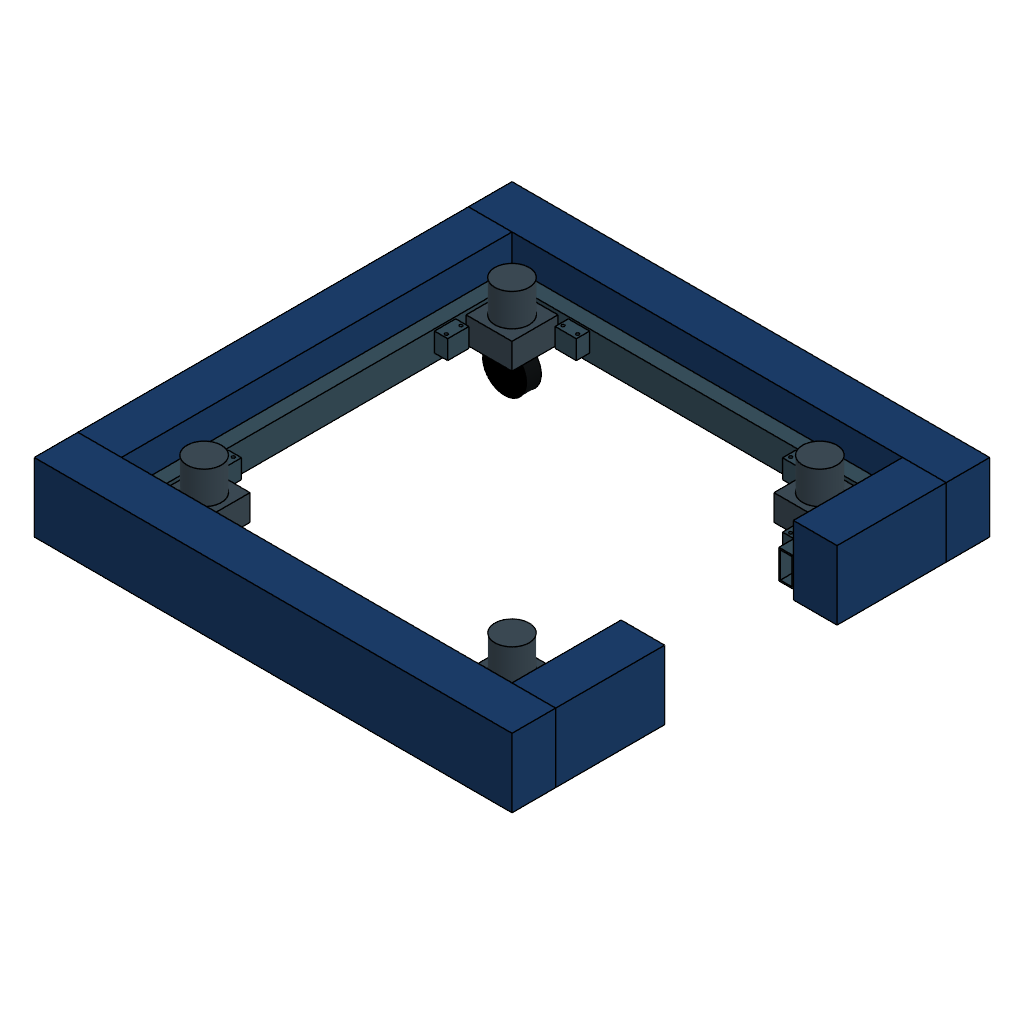
own-zone-public (Autodesk Fusion 360 design; units mm, degrees)
part number: 2026-11-19-16-10-08-669
part number: 2026-11-19-16-10-12-330
part number: 2026-11-19-16-10-12-467
part number: 2026-11-19-16-10-12-522
part number: 2026-11-19-16-10-12-574
part number: 2026-11-19-16-10-12-622
part number: 2026-11-19-16-10-12-689
part number: 2026-11-19-16-10-12-752
part number: 2026-11-19-16-10-12-805
part number: 2026-11-19-16-10-12-862
part number: 2026-11-19-16-10-12-931
part number: 2026-11-19-16-10-13-004
part number: 2026-11-19-16-10-13-091
part number: 2026-11-19-16-10-13-172
part number: 2026-11-19-16-10-13-257
part number: 2026-11-19-16-10-13-348
part number: 2026-11-19-16-10-13-447
part number: 2026-11-19-16-10-13-556
part number: 2026-11-19-16-10-13-649
part number: 2026-11-19-16-10-13-740
part number: 2026-11-19-16-10-13-823
part number: 2026-11-19-16-10-13-917
part number: 2026-11-19-16-10-14-002
part number: 2026-11-19-16-10-14-092
part number: 2026-11-19-16-10-14-189
part number: 2026-11-19-16-10-14-316
part number: 2026-11-19-16-10-14-442
part number: 2026-11-19-16-10-14-569
part number: 2026-11-19-16-10-14-696
part number: 2026-11-19-16-10-14-815
part number: 2026-11-19-16-10-14-952
Autodesk Fusion 360 part; units mm, degrees
sketch "Editable cross section" plane through (0, 0, 0) normal (0, 0, 1) x (1, 0, 0) in component "left perimeter tube"
  line L0 (-12.7, -25.4) -> (12.7, -25.4)
  line L1 (12.7, -25.4) -> (12.7, 25.4)
  line L2 (12.7, 25.4) -> (-12.7, 25.4)
  line L3 (-12.7, 25.4) -> (-12.7, -25.4)
  line L4 (-10.16, -22.86) -> (10.16, -22.86)
  line L5 (10.16, -22.86) -> (10.16, 22.86)
  line L6 (10.16, 22.86) -> (-10.16, 22.86)
  line L7 (-10.16, 22.86) -> (-10.16, -22.86)
extrude "Stock length" add sketch "Editable cross section" along normal blind 680 makes body 1 in component "left perimeter tube"
sketch "Editable cross section (2)" plane through (0, 0, 0) normal (0, 0, 1) x (1, 0, 0) in component "left front return"
  line L0 (-12.7, -25.4) -> (12.7, -25.4)
  line L1 (12.7, -25.4) -> (12.7, 25.4)
  line L2 (12.7, 25.4) -> (-12.7, 25.4)
  line L3 (-12.7, 25.4) -> (-12.7, -25.4)
  line L4 (-10.16, -22.86) -> (10.16, -22.86)
  line L5 (10.16, -22.86) -> (10.16, 22.86)
  line L6 (10.16, 22.86) -> (-10.16, 22.86)
  line L7 (-10.16, 22.86) -> (-10.16, -22.86)
extrude "Stock length'" add sketch "Editable cross section (2)" along normal blind 164.6 separate body makes body 2 in component "left front return"
sketch "Editable cross section (3)" plane through (0, 0, 0) normal (0, 0, 1) x (1, 0, 0) in component "left blue side bumper"
  line L0 (-416, -38) -> (416, -38)
  line L1 (416, -38) -> (416, 38)
  line L2 (416, 38) -> (-416, 38)
  line L3 (-416, 38) -> (-416, -38)
extrude "Stock length''" add sketch "Editable cross section (3)" along normal blind 120 separate body makes body 3 in component "left blue side bumper"
sketch "Editable cross section (4)" plane through (0, 0, 0) normal (0, 0, 1) x (1, 0, 0) in component "left blue front bumper"
  line L0 (-38, -95) -> (38, -95)
  line L1 (38, -95) -> (38, 95)
  line L2 (38, 95) -> (-38, 95)
  line L3 (-38, 95) -> (-38, -95)
extrude "Stock length'''" add sketch "Editable cross section (4)" along normal blind 120 separate body makes body 4 in component "left blue front bumper"
sketch "Editable cross section (5)" plane through (0, 0, 0) normal (0, 0, 1) x (1, 0, 0) in component "right perimeter tube"
  line L0 (-12.7, -25.4) -> (12.7, -25.4)
  line L1 (12.7, -25.4) -> (12.7, 25.4)
  line L2 (12.7, 25.4) -> (-12.7, 25.4)
  line L3 (-12.7, 25.4) -> (-12.7, -25.4)
  line L4 (-10.16, -22.86) -> (10.16, -22.86)
  line L5 (10.16, -22.86) -> (10.16, 22.86)
  line L6 (10.16, 22.86) -> (-10.16, 22.86)
  line L7 (-10.16, 22.86) -> (-10.16, -22.86)
extrude "Stock length''''" add sketch "Editable cross section (5)" along normal blind 680 separate body makes body 5 in component "right perimeter tube"
sketch "Editable cross section (6)" plane through (0, 0, 0) normal (0, 0, 1) x (1, 0, 0) in component "right front return"
  line L0 (-12.7, -25.4) -> (12.7, -25.4)
  line L1 (12.7, -25.4) -> (12.7, 25.4)
  line L2 (12.7, 25.4) -> (-12.7, 25.4)
  line L3 (-12.7, 25.4) -> (-12.7, -25.4)
  line L4 (-10.16, -22.86) -> (10.16, -22.86)
  line L5 (10.16, -22.86) -> (10.16, 22.86)
  line L6 (10.16, 22.86) -> (-10.16, 22.86)
  line L7 (-10.16, 22.86) -> (-10.16, -22.86)
extrude "Stock length'''''" add sketch "Editable cross section (6)" along normal blind 164.6 separate body makes body 6 in component "right front return"
sketch "Editable cross section (7)" plane through (0, 0, 0) normal (0, 0, 1) x (1, 0, 0) in component "right blue side bumper"
  line L0 (-416, -38) -> (416, -38)
  line L1 (416, -38) -> (416, 38)
  line L2 (416, 38) -> (-416, 38)
  line L3 (-416, 38) -> (-416, -38)
extrude "Stock length''''''" add sketch "Editable cross section (7)" along normal blind 120 separate body makes body 7 in component "right blue side bumper"
sketch "Editable cross section (8)" plane through (0, 0, 0) normal (0, 0, 1) x (1, 0, 0) in component "right blue front bumper"
  line L0 (-38, -95) -> (38, -95)
  line L1 (38, -95) -> (38, 95)
  line L2 (38, 95) -> (-38, 95)
  line L3 (-38, 95) -> (-38, -95)
extrude "Stock length'''''''" add sketch "Editable cross section (8)" along normal blind 120 separate body makes body 8 in component "right blue front bumper"
sketch "Editable cross section (9)" plane through (0, 0, 0) normal (0, 0, 1) x (1, 0, 0) in component "rear perimeter tube"
  line L0 (-12.7, -25.4) -> (12.7, -25.4)
  line L1 (12.7, -25.4) -> (12.7, 25.4)
  line L2 (12.7, 25.4) -> (-12.7, 25.4)
  line L3 (-12.7, 25.4) -> (-12.7, -25.4)
  line L4 (-10.16, -22.86) -> (10.16, -22.86)
  line L5 (10.16, -22.86) -> (10.16, 22.86)
  line L6 (10.16, 22.86) -> (-10.16, 22.86)
  line L7 (-10.16, 22.86) -> (-10.16, -22.86)
extrude "Stock length''''''''" add sketch "Editable cross section (9)" along normal blind 629.2 separate body makes body 9 in component "rear perimeter tube"
sketch "Editable cross section (10)" plane through (0, 0, 0) normal (0, 0, 1) x (1, 0, 0) in component "rear blue bumper"
  line L0 (-38, -340) -> (38, -340)
  line L1 (38, -340) -> (38, 340)
  line L2 (38, 340) -> (-38, 340)
  line L3 (-38, 340) -> (-38, -340)
extrude "Stock length'''''''''" add sketch "Editable cross section (10)" along normal blind 120 separate body makes body 10 in component "rear blue bumper"
sketch "Editable cross section (11)" plane through (0, 0, 0) normal (0, 0, 1) x (1, 0, 0) in component "front left module tab spacer 1"
  line L0 (-18.5, -11.55) -> (18.5, -11.55)
  line L1 (18.5, -11.55) -> (18.5, 11.55)
  line L2 (18.5, 11.55) -> (-18.5, 11.55)
  line L3 (-18.5, 11.55) -> (-18.5, -11.55)
  circle A0 centre (12.85, -3.3) radius 2.65
  circle A1 centre (-12.55, -3.3) radius 2.65
extrude "Stock length''''''''''" add sketch "Editable cross section (11)" along normal blind 33.18 separate body makes body 11 in component "front left module tab spacer 1"
sketch "Editable cross section (12)" plane through (0, 0, 0) normal (0, 0, 1) x (1, 0, 0) in component "front left module tab spacer 2"
  line L0 (-11.55, -18.5) -> (11.55, -18.5)
  line L1 (11.55, -18.5) -> (11.55, 18.5)
  line L2 (11.55, 18.5) -> (-11.55, 18.5)
  line L3 (-11.55, 18.5) -> (-11.55, -18.5)
  circle A0 centre (-3.3, 12.85) radius 2.65
  circle A1 centre (-3.3, -12.55) radius 2.65
extrude "Stock length'''''''''''" add sketch "Editable cross section (12)" along normal blind 33.18 separate body makes body 12 in component "front left module tab spacer 2"
sketch "Editable cross section (13)" plane through (0, 0, 0) normal (0, 0, 1) x (1, 0, 0) in component "front right module tab spacer 1"
  line L0 (-11.55, -18.5) -> (11.55, -18.5)
  line L1 (11.55, -18.5) -> (11.55, 18.5)
  line L2 (11.55, 18.5) -> (-11.55, 18.5)
  line L3 (-11.55, 18.5) -> (-11.55, -18.5)
  circle A0 centre (-3.3, -12.85) radius 2.65
  circle A1 centre (-3.3, 12.55) radius 2.65
extrude "Stock length''''''''''''" add sketch "Editable cross section (13)" along normal blind 33.18 separate body makes body 13 in component "front right module tab spacer 1"
sketch "Editable cross section (14)" plane through (0, 0, 0) normal (0, 0, 1) x (1, 0, 0) in component "front right module tab spacer 2"
  line L0 (-18.5, -11.55) -> (18.5, -11.55)
  line L1 (18.5, -11.55) -> (18.5, 11.55)
  line L2 (18.5, 11.55) -> (-18.5, 11.55)
  line L3 (-18.5, 11.55) -> (-18.5, -11.55)
  circle A0 centre (12.85, 3.3) radius 2.65
  circle A1 centre (-12.55, 3.3) radius 2.65
extrude "Stock length'''''''''''''" add sketch "Editable cross section (14)" along normal blind 33.18 separate body makes body 14 in component "front right module tab spacer 2"
sketch "Editable cross section (15)" plane through (0, 0, 0) normal (0, 0, 1) x (1, 0, 0) in component "rear left module tab spacer 1"
  line L0 (-11.55, -18.5) -> (11.55, -18.5)
  line L1 (11.55, -18.5) -> (11.55, 18.5)
  line L2 (11.55, 18.5) -> (-11.55, 18.5)
  line L3 (-11.55, 18.5) -> (-11.55, -18.5)
  circle A0 centre (3.3, 12.85) radius 2.65
  circle A1 centre (3.3, -12.55) radius 2.65
extrude "Stock length''''''''''''''" add sketch "Editable cross section (15)" along normal blind 33.18 separate body makes body 15 in component "rear left module tab spacer 1"
sketch "Editable cross section (16)" plane through (0, 0, 0) normal (0, 0, 1) x (1, 0, 0) in component "rear left module tab spacer 2"
  line L0 (-18.5, -11.55) -> (18.5, -11.55)
  line L1 (18.5, -11.55) -> (18.5, 11.55)
  line L2 (18.5, 11.55) -> (-18.5, 11.55)
  line L3 (-18.5, 11.55) -> (-18.5, -11.55)
  circle A0 centre (-12.85, -3.3) radius 2.65
  circle A1 centre (12.55, -3.3) radius 2.65
extrude "Stock length'''''''''''''''" add sketch "Editable cross section (16)" along normal blind 33.18 separate body makes body 16 in component "rear left module tab spacer 2"
sketch "Editable cross section (17)" plane through (0, 0, 0) normal (0, 0, 1) x (1, 0, 0) in component "rear right module tab spacer 1"
  line L0 (-18.5, -11.55) -> (18.5, -11.55)
  line L1 (18.5, -11.55) -> (18.5, 11.55)
  line L2 (18.5, 11.55) -> (-18.5, 11.55)
  line L3 (-18.5, 11.55) -> (-18.5, -11.55)
  circle A0 centre (-12.85, 3.3) radius 2.65
  circle A1 centre (12.55, 3.3) radius 2.65
extrude "Stock length''''''''''''''''" add sketch "Editable cross section (17)" along normal blind 33.18 separate body makes body 17 in component "rear right module tab spacer 1"
sketch "Editable cross section (18)" plane through (0, 0, 0) normal (0, 0, 1) x (1, 0, 0) in component "rear right module tab spacer 2"
  line L0 (-11.55, -18.5) -> (11.55, -18.5)
  line L1 (11.55, -18.5) -> (11.55, 18.5)
  line L2 (11.55, 18.5) -> (-11.55, 18.5)
  line L3 (-11.55, 18.5) -> (-11.55, -18.5)
  circle A0 centre (3.3, -12.85) radius 2.65
  circle A1 centre (3.3, 12.55) radius 2.65
extrude "Stock length'''''''''''''''''" add sketch "Editable cross section (18)" along normal blind 33.18 separate body makes body 18 in component "rear right module tab spacer 2"
sketch "Editable cross section (19)" plane through (0, 0, 0) normal (0, 0, 1) x (1, 0, 0) in component "front left public wheel"
  circle A0 centre (0, 0) radius 38.1
extrude "Stock length''''''''''''''''''" add sketch "Editable cross section (19)" along normal blind 26 separate body makes body 19 in component "front left public wheel"
sketch "Editable cross section (20)" plane through (0, 0, 0) normal (0, 0, 1) x (1, 0, 0) in component "front left public drive housing"
  line L0 (-40, -40) -> (40, -40)
  line L1 (40, -40) -> (40, 40)
  line L2 (40, 40) -> (-40, 40)
  line L3 (-40, 40) -> (-40, -40)
extrude "Stock length'''''''''''''''''''" add sketch "Editable cross section (20)" along normal blind 45 separate body makes body 20 in component "front left public drive housing"
sketch "Editable cross section (21)" plane through (0, 0, 0) normal (0, 0, 1) x (1, 0, 0) in component "front left public motor reserve"
  circle A0 centre (0, 0) radius 29.9
extrude "Stock length''''''''''''''''''''" add sketch "Editable cross section (21)" along normal blind 56.46 separate body makes body 21 in component "front left public motor reserve"
sketch "Editable cross section (22)" plane through (0, 0, 0) normal (0, 0, 1) x (1, 0, 0) in component "front right public wheel"
  circle A0 centre (0, 0) radius 38.1
extrude "Stock length'''''''''''''''''''''" add sketch "Editable cross section (22)" along normal blind 26 separate body makes body 22 in component "front right public wheel"
sketch "Editable cross section (23)" plane through (0, 0, 0) normal (0, 0, 1) x (1, 0, 0) in component "front right public drive housing"
  line L0 (-40, -40) -> (40, -40)
  line L1 (40, -40) -> (40, 40)
  line L2 (40, 40) -> (-40, 40)
  line L3 (-40, 40) -> (-40, -40)
extrude "Stock length''''''''''''''''''''''" add sketch "Editable cross section (23)" along normal blind 45 separate body makes body 23 in component "front right public drive housing"
sketch "Editable cross section (24)" plane through (0, 0, 0) normal (0, 0, 1) x (1, 0, 0) in component "front right public motor reserve"
  circle A0 centre (0, 0) radius 29.9
extrude "Stock length'''''''''''''''''''''''" add sketch "Editable cross section (24)" along normal blind 56.46 separate body makes body 24 in component "front right public motor reserve"
sketch "Editable cross section (25)" plane through (0, 0, 0) normal (0, 0, 1) x (1, 0, 0) in component "rear left public wheel"
  circle A0 centre (0, 0) radius 38.1
extrude "Stock length''''''''''''''''''''''''" add sketch "Editable cross section (25)" along normal blind 26 separate body makes body 25 in component "rear left public wheel"
sketch "Editable cross section (26)" plane through (0, 0, 0) normal (0, 0, 1) x (1, 0, 0) in component "rear left public drive housing"
  line L0 (-40, -40) -> (40, -40)
  line L1 (40, -40) -> (40, 40)
  line L2 (40, 40) -> (-40, 40)
  line L3 (-40, 40) -> (-40, -40)
extrude "Stock length'''''''''''''''''''''''''" add sketch "Editable cross section (26)" along normal blind 45 separate body makes body 26 in component "rear left public drive housing"
sketch "Editable cross section (27)" plane through (0, 0, 0) normal (0, 0, 1) x (1, 0, 0) in component "rear left public motor reserve"
  circle A0 centre (0, 0) radius 29.9
extrude "Stock length''''''''''''''''''''''''''" add sketch "Editable cross section (27)" along normal blind 56.46 separate body makes body 27 in component "rear left public motor reserve"
sketch "Editable cross section (28)" plane through (0, 0, 0) normal (0, 0, 1) x (1, 0, 0) in component "rear right public wheel"
  circle A0 centre (0, 0) radius 38.1
extrude "Stock length'''''''''''''''''''''''''''" add sketch "Editable cross section (28)" along normal blind 26 separate body makes body 28 in component "rear right public wheel"
sketch "Editable cross section (29)" plane through (0, 0, 0) normal (0, 0, 1) x (1, 0, 0) in component "rear right public drive housing"
  line L0 (-40, -40) -> (40, -40)
  line L1 (40, -40) -> (40, 40)
  line L2 (40, 40) -> (-40, 40)
  line L3 (-40, 40) -> (-40, -40)
extrude "Stock length''''''''''''''''''''''''''''" add sketch "Editable cross section (29)" along normal blind 45 separate body makes body 29 in component "rear right public drive housing"
sketch "Editable cross section (30)" plane through (0, 0, 0) normal (0, 0, 1) x (1, 0, 0) in component "rear right public motor reserve"
  circle A0 centre (0, 0) radius 29.9
extrude "Stock length'''''''''''''''''''''''''''''" add sketch "Editable cross section (30)" along normal blind 56.46 separate body makes body 30 in component "rear right public motor reserve"
component "left perimeter tube" placed x (0, 1, 0) y (0, 0, 1) z (1, 0, 0) at (-340, 327.3, 89.4)
component "left front return" placed x (-1, 0, 0) y (0, 0, 1) z (0, 1, 0) at (327.3, 150, 89.4)
component "left blue side bumper" placed x (1, 0, 0) y (0, 1, 0) z (0, 0, 1) at (0, 378, 48)
component "left blue front bumper" placed x (1, 0, 0) y (0, 1, 0) z (0, 0, 1) at (378, 245, 48)
component "right perimeter tube" placed x (0, 1, 0) y (0, 0, 1) z (1, 0, 0) at (-340, -327.3, 89.4)
component "right front return" placed x (-1, 0, 0) y (0, 0, 1) z (0, 1, 0) at (327.3, -314.6, 89.4)
component "right blue side bumper" placed x (1, 0, 0) y (0, 1, 0) z (0, 0, 1) at (0, -378, 48)
component "right blue front bumper" placed x (1, 0, 0) y (0, 1, 0) z (0, 0, 1) at (378, -245, 48)
component "rear perimeter tube" placed x (-1, 0, 0) y (0, 0, 1) z (0, 1, 0) at (-327.3, -314.6, 89.4)
component "rear blue bumper" placed x (1, 0, 0) y (0, 1, 0) z (0, 0, 1) at (-378, 0, 48)
component "front left module tab spacer 1" placed x (1, 0, 0) y (0, 1, 0) z (0, 0, 1) at (198, 303.05, 78.32)
component "front left module tab spacer 2" placed x (1, 0, 0) y (0, 1, 0) z (0, 0, 1) at (303.05, 198, 78.32)
component "front right module tab spacer 1" placed x (1, 0, 0) y (0, 1, 0) z (0, 0, 1) at (303.05, -198, 78.32)
component "front right module tab spacer 2" placed x (1, 0, 0) y (0, 1, 0) z (0, 0, 1) at (198, -303.05, 78.32)
component "rear left module tab spacer 1" placed x (1, 0, 0) y (0, 1, 0) z (0, 0, 1) at (-303.05, 198, 78.32)
component "rear left module tab spacer 2" placed x (1, 0, 0) y (0, 1, 0) z (0, 0, 1) at (-198, 303.05, 78.32)
component "rear right module tab spacer 1" placed x (1, 0, 0) y (0, 1, 0) z (0, 0, 1) at (-198, -303.05, 78.32)
component "rear right module tab spacer 2" placed x (1, 0, 0) y (0, 1, 0) z (0, 0, 1) at (-303.05, -198, 78.32)
component "front left public wheel" placed x (-1, 0, 0) y (0, 0, 1) z (0, 1, 0) at (268, 255, 38.1)
component "front left public drive housing" placed x (1, 0, 0) y (0, 1, 0) z (0, 0, 1) at (268, 268, 70)
component "front left public motor reserve" placed x (1, 0, 0) y (0, 1, 0) z (0, 0, 1) at (268, 268, 115)
component "front right public wheel" placed x (-1, 0, 0) y (0, 0, 1) z (0, 1, 0) at (268, -281, 38.1)
component "front right public drive housing" placed x (1, 0, 0) y (0, 1, 0) z (0, 0, 1) at (268, -268, 70)
component "front right public motor reserve" placed x (1, 0, 0) y (0, 1, 0) z (0, 0, 1) at (268, -268, 115)
component "rear left public wheel" placed x (-1, 0, 0) y (0, 0, 1) z (0, 1, 0) at (-268, 255, 38.1)
component "rear left public drive housing" placed x (1, 0, 0) y (0, 1, 0) z (0, 0, 1) at (-268, 268, 70)
component "rear left public motor reserve" placed x (1, 0, 0) y (0, 1, 0) z (0, 0, 1) at (-268, 268, 115)
component "rear right public wheel" placed x (-1, 0, 0) y (0, 0, 1) z (0, 1, 0) at (-268, -281, 38.1)
component "rear right public drive housing" placed x (1, 0, 0) y (0, 1, 0) z (0, 0, 1) at (-268, -268, 70)
component "rear right public motor reserve" placed x (1, 0, 0) y (0, 1, 0) z (0, 0, 1) at (-268, -268, 115)
named bodies: "left perimeter tube", "left front return", "left blue side bumper", "left blue front bumper", "right perimeter tube", "right front return", "right blue side bumper", "right blue front bumper", "rear perimeter tube", "rear blue bumper", "front left module tab spacer 1", "front left module tab spacer 2", "front right module tab spacer 1", "front right module tab spacer 2", "rear left module tab spacer 1", "rear left module tab spacer 2", "rear right module tab spacer 1", "rear right module tab spacer 2", "front left public wheel", "front left public drive housing", "front left public motor reserve", "front right public wheel", "front right public drive housing", "front right public motor reserve", "rear left public wheel", "rear left public drive housing", "rear left public motor reserve", "rear right public wheel", "rear right public drive housing", "rear right public motor reserve"
